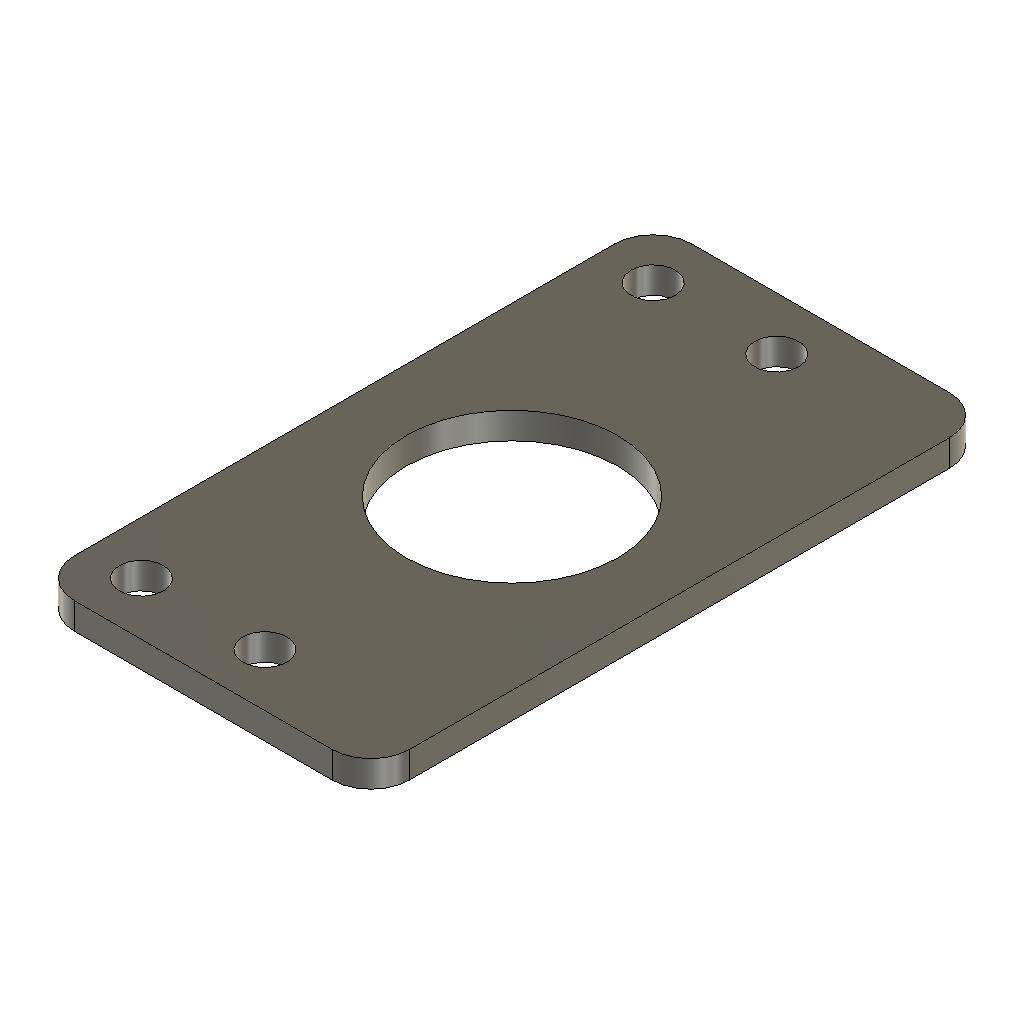
switch_plate (Autodesk Fusion 360 design; units mm, degrees)
Autodesk Fusion 360 part; units mm, degrees
sketch "Sketch1" plane through (0, 0, 0) normal (0, 0, 1) x (1, 0, 0)
  line L0 (0, 0) -> (19, 0)
  line L1 (19, 0) -> (19, -35)
  line L2 (19, -35) -> (0, -35)
  line L3 (0, -35) -> (0, 0)
  circle A0 centre (3, -3) radius 1.25
  circle A1 centre (10, -3) radius 1.25
  circle A2 centre (3, -32) radius 1.25
  circle A3 centre (10, -32) radius 1.25
  line L4 (0, -17.5) -> (19, -17.5) construction
  circle A4 centre (9.5, -17.5) radius 6
  dimension "d1" = 35
  dimension "d2" = 19
  dimension "d3" = 2.5
  dimension "d4" = 2.5
  dimension "d5" = 7
  dimension "d6" = 3
  dimension "d7" = 3
  dimension "d8" = 3
  dimension "d9" = 2.5
  dimension "d10" = 2.5
  dimension "d11" = 7
  dimension "d12" = 29
  dimension "d13" = 3
  dimension "d14" = 7
  dimension "d15" = 12
  constraint horizontal L0
  constraint vertical L1
  constraint horizontal L2
  constraint vertical L3
  constraint coincident L0.start L3.end
  constraint midpoint L3 L4.start
  constraint midpoint L1 L4.end
  constraint midpoint L4 A4.centre
  measures "d1" distance of L0.end L1.end
  measures "d2" distance of L1.end L2.end
  measures "d3" diameter of A0
  measures "d4" diameter of A1
  measures "d5" horizontal distance of A0.centre A1.centre
  measures "d6" distance of L3 A0.centre
  measures "d7" distance of L0 A1.centre
  measures "d8" distance of L0 A0.centre
  measures "d9" diameter of A2
  measures "d10" diameter of A3
  measures "d11" horizontal distance of A3.centre A2.centre
  measures "d12" distance of A0.centre A2.centre
  measures "d13" distance of L3 A2.centre
  measures "d14" distance of A3.centre A2.centre
  measures "d15" diameter of A4
extrude "Extrude1" add sketch "Sketch1" along normal blind 1.5
fillet "Fillet1" radius 2.2 4 edges at (0, 0, 0.75) (19, 0, 0.75) (19, -35, 0.75) (0, -35, 0.75)
